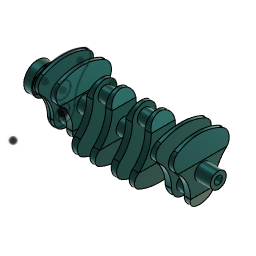
L5_Dobrescu_Diana (Autodesk Fusion 360 design; units mm, degrees)
Autodesk Fusion 360 part; units mm, degrees
sketch "Sketch1" plane through (0, 0, 0) normal (1, 0, 0) x (0, 1, 0)
  circle A0 centre (0, 0) radius 17.5
  arc A1 (-30, 0) -> (-61.5875, 70.7379) centre (-125, 0) ccw
  arc A2 (61.5875, 70.7379) -> (30, 0) centre (125, 0) ccw
  arc A3 (56.125, 111.6915) -> (-56.125, 111.6915) centre (0, 0) ccw
  arc A4 (-30, 0) -> (30, 0) centre (0, 0) ccw
  circle A5 centre (0, 47.5) radius 20
  arc A6 (-56.125, 111.6915) -> (-61.5875, 70.7379) centre (-44.9, 89.3532) ccw
  arc A7 (61.5875, 70.7379) -> (56.125, 111.6915) centre (44.9, 89.3532) ccw
  dimension "d2" = 35
  dimension "d3" = 60
  dimension "d4" = 190
  dimension "d5" = 190
  dimension "d6" = 50
  dimension "d7" = 50
  dimension "d8" = 47.5
  dimension "d9" = 40
  dimension "d38" = 125
  constraint coincident A0.centre A3.centre
  constraint tangent A1 A6
  constraint tangent A2 A7
  constraint horizontal A2.centre A1.centre
  constraint vertical A0.centre A5.centre
  constraint tangent A3 A6
  constraint tangent A3 A7
  constraint tangent A2 A4
  constraint tangent A1 A4
  constraint horizontal A0.centre A1.centre
  measures "d2" diameter of A0
  measures "d3" diameter of A4
  measures "d4" diameter of A2
  measures "d5" diameter of A1
  measures "d6" diameter of A6
  measures "d7" diameter of A7
  measures "d8" distance of A0.centre A5.centre
  measures "d9" diameter of A5
  measures "d38" radius of A3
extrude "Extrude1" add sketch "Sketch1" along normal mid plane 16 contours A0 | A1 A2 A3 A4 A6 A7 | A5 makes body 1
extrude "Extrude2" add sketch "Sketch1" against normal blind 43 separate body contours A5 makes body 2
extrude "Extrude3" add sketch "Sketch1" along normal blind 40 separate body contours A0 makes body 3
extrude "Extrude5" add sketch "Sketch1" along normal blind 16 from surface at 40 contours A0 | A1 A2 A3 A4 A6 A7 | A5 bodies 3
sketch "Sketch2" plane through (0, 0, 0) normal (0, 1, 0) x (1, 0, 0)
  line L0 (-8, 30) -> (-8, 0)
  line L1 (-8, 0) -> (-8, -70.7379)
  line L2 (-8, -70.7379) -> (-8, -111.6915)
  line L3 (-8, -111.6915) -> (-8, -125)
  line L4 (8, -70.7379) -> (8, 0)
  line L5 (8, -111.6915) -> (8, -70.7379)
  line L6 (8, -125) -> (8, -111.6915)
  line L7 (8, 0) -> (8, 30)
  line L8 (-8, -125) -> (8, -125)
  line L9 (-8, 30) -> (8, 30)
  line L10 (-43, -47.5) -> (-43, -67.5)
  line L11 (-43, -27.5) -> (-43, -47.5)
  line L12 (0, -47.5) -> (0, -27.5)
  line L13 (0, -67.5) -> (0, -47.5)
  line L14 (0, -27.5) -> (-43, -27.5)
  line L15 (0, -67.5) -> (-43, -67.5)
  line L16 (40, 17.5) -> (40, 30)
  line L17 (40, -17.5) -> (40, -70.7379)
  line L18 (40, -111.6915) -> (40, -70.7379)
  line L19 (40, -125) -> (40, -111.6915)
  line L20 (56, -70.7379) -> (56, 0)
  line L21 (56, -111.6915) -> (56, -70.7379)
  line L22 (56, -125) -> (56, -111.6915)
  line L23 (56, 0) -> (56, 30)
  line L24 (0, 0) -> (0, 17.5)
  line L25 (0, -17.5) -> (0, 0)
  line L26 (40, -125) -> (56, -125)
  line L27 (40, 30) -> (56, 30)
  line L28 (0, -17.5) -> (40, -17.5)
  line L29 (0, 17.5) -> (40, 17.5)
  line L30 (56, -70.7379) -> (48, -125)
  line L31 (-8, -70.7379) -> (0, -125)
  line L32 (-8, 0) -> (0, 30)
  line L33 (56, 0) -> (48, 30)
  constraint coincident L20.start L21.end
  constraint midpoint L26 L30.end
  constraint coincident L1.end L2.start
  constraint midpoint L8 L31.end
  constraint coincident L0.end L1.start
  constraint midpoint L9 L32.end
  constraint coincident L20.end L23.start
  constraint midpoint L27 L33.end
extrude "Extrude6" cut sketch "Sketch2" along normal through all and the other way through all contours L0 L9 L32 | L2 L3 L8 L31 | L23 L27 L33 | L21 L22 L26 L30 bodies 1 3
combine "Combine1" operation add target body 3 tool bodies 1 2
copy_body "CopyPasteBodies1" bodies 3 makes body 4
move_body "Move1" bodies 4 to x (1, 0, 0) y (0, -1, 0) z (0, 0, -1) at (99, 0, 95)
copy_body "CopyPasteBodies2" bodies 4 makes body 5
move_body "Move2" bodies 5 to x (1, 0, 0) y (0, 1, 0) z (0, 0, 1) at (99, 0, 0)
copy_body "CopyPasteBodies3" bodies 5 makes body 6
move_body "Move3" bodies 6 to x (1, 0, 0) y (0, 1, 0) z (0, 0, 1) at (0, 0, 0)
copy_body "CopyPasteBodies4" bodies 5 makes body 7
move_body "Move4" bodies 7 to x (1, 0, 0) y (0, -1, 0) z (0, 0, -1) at (99, 0, 95)
sketch "Sketch3" plane through (353, 0, 0) normal (1, 0, 0) x (0, 1, 0)
  line L0 (-30, 0) -> (30, 0)
  arc A0 (61.5875, 70.7379) -> (30, 0) centre (125, 0) ccw
  line L1 (61.5875, 70.7379) -> (-61.5875, 70.7379)
  arc A1 (-30, 0) -> (-61.5875, 70.7379) centre (-125, 0) ccw
  circle A2 centre (0, 47.5) radius 10
  circle A3 centre (0, 47.5) radius 20
  dimension "d24" = 47.5
  dimension "d25" = 20
  dimension "d26" = 40
  constraint concentric A2 A3
  measures "d24" distance of origin A2.centre
  measures "d25" diameter of A2
  measures "d26" diameter of A3
extrude "Extrude7" add sketch "Sketch3" along normal blind 40 contours A3 bodies 7
sketch "Sketch4" plane through (-43, 0, 0) normal (-1, 0, 0) x (0, -1, 0)
  circle A0 centre (0, 47.5) radius 20
  circle A1 centre (0, 47.5) radius 35
  circle A2 centre (0, 75.5) radius 5
  circle A3 centre (-24.2487, 61.5) radius 5
  circle A4 centre (-24.2487, 33.5) radius 5
  circle A5 centre (0, 19.5) radius 5
  circle A6 centre (24.2487, 33.5) radius 5
  circle A7 centre (24.2487, 61.5) radius 5
  dimension "d29" = 70
  dimension "d30" = 28
  dimension "d31" = 10
  dimension "d33" = 360
  constraint concentric A0 A1
  measures "d29" diameter of A1
  measures "d30" distance of A0.centre A2.centre
  measures "d31" diameter of A2
extrude "Extrude8" add sketch "Sketch4" along normal blind 20 bodies 3 4 5 6 7
extrude "Extrude9" add 1 faces at (-43, 1.4835, 53.9995) along direction (-1, 0, 0) blind 20 on bodies 3 bodies 3
